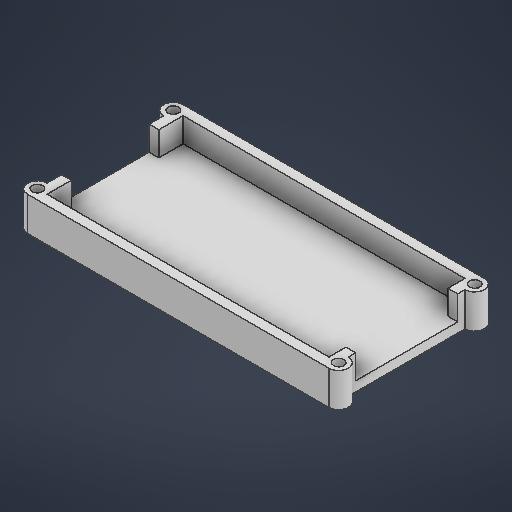
# Autodesk Inventor part: CASE
Saved by Autodesk Inventor 2027.1 (Build 311270010, 270A)
## iProperties
Created: 2026-09-25
Part Number: CASE
Material: 일반
Document SubType Name: Modeling
Designer: work
Density: 1 g/cm^3
Appearance: 기본값
Author: work
Autodesk Inventor part; units mm, degrees
ref_plane "YZ Plane" through (0, 0, 0) normal (1, 0, 0) x (0, 1, 0)
ref_plane "XZ Plane" through (0, 0, 0) normal (0, 1, 0) x (-1, 0, 0)
ref_plane "XY Plane" through (0, 0, 0) normal (0, 0, 1) x (1, 0, 0)
sketch "스케치1" plane through (0, 0, 0) normal (0, 1, 0) x (-1, 0, 0)
  line L0 (0, 0) -> (58, 0)
  line L1 (58, 0) -> (58, -28)
  line L2 (58, -28) -> (0, -28)
  line L3 (0, -28) -> (0, 0)
  line L4 (-2, -30) -> (60, -30)
  line L5 (60, -30) -> (60, 2)
  line L6 (60, 2) -> (-2, 2)
  line L7 (-2, 2) -> (-2, -30)
  line L8 (0, -3.5) -> (-2, -3.5)
  line L9 (-2, -3.5) -> (-2, -24.5)
  line L10 (-2, -24.5) -> (0, -24.5)
  line L11 (0, -24.5) -> (0, -3.5)
  line L12 (58, -5) -> (60, -5)
  line L13 (60, -5) -> (60, -23)
  line L14 (60, -23) -> (58, -23)
  line L15 (58, -23) -> (58, -5)
  circle A0 centre (60, 0) radius 1.1
  line L16 (58, -14) -> (60, -14) construction
  circle A1 centre (60, 0) radius 2
  circle A2 centre (60, -28) radius 1.1
  circle A3 centre (60, -28) radius 2
  circle A4 centre (-2, 0) radius 1.1
  circle A5 centre (-2, 0) radius 2
  circle A6 centre (-2, -28) radius 1.1
  circle A7 centre (-2, -28) radius 2
  point P0 (0, -14)
  point P1 (-2, -14)
  point P2 (59, -23)
  point P3 (59, -5)
  point P4 (60, -26)
  point P5 (-2, -26)
  point P6 (60, -2)
  point P7 (-2, -2)
  dimension "d0" = 58
  dimension "d1" = 28
  dimension "d2" = 2
  dimension "d3" = 21
  dimension "d4" = 18
  dimension "d5" = 2.2
  dimension "d6" = 2.2
  constraints: 34 end point, 10 midpoint, 8 parallel, 6 centre point, 4 coincident, 4 horizontal, 4 perpendicular, 4 symmetric about line, 2 horizontal alignment, 2 point on line, 13 other
  measures "d0" distance of L1.end L2.end
  measures "d1" distance of L0.end L1.end
  measures "d2" distance between parallel lines of L2 L4
  measures "d3" distance of L8.end L9.end
  measures "d4" distance of point (59, -23) point (59, -5)
  measures "d5" diameter of A0
  measures "d6" diameter of A4
extrude "돌출1" add sketch "스케치1" along normal blind 7 contours A5 L6 A1 L0 | A5 L7 A4 | L3 L8 L7 A5 | A1 L5 L12 L1 | A1 L5 A0 | L7 A4 A5 | A1 L5 A0 | L3 A7 L7 L10 | L14 L5 A3 L1 | L2 A3 L4 A7 | A7 L7 A6 | A3 L5 A2 | A7 L7 A6 | L5 A2 A3
extrude "돌출2" add sketch "스케치1" along normal blind 2 contours L0 L1 L2 L3 | L3 L10 L7 L8 | L12 L5 L14 L1 | A4 L7 | L7 A4 | A0 L5 | L5 A0 | A6 L7 | L7 A6 | A2 L5 | L5 A2
